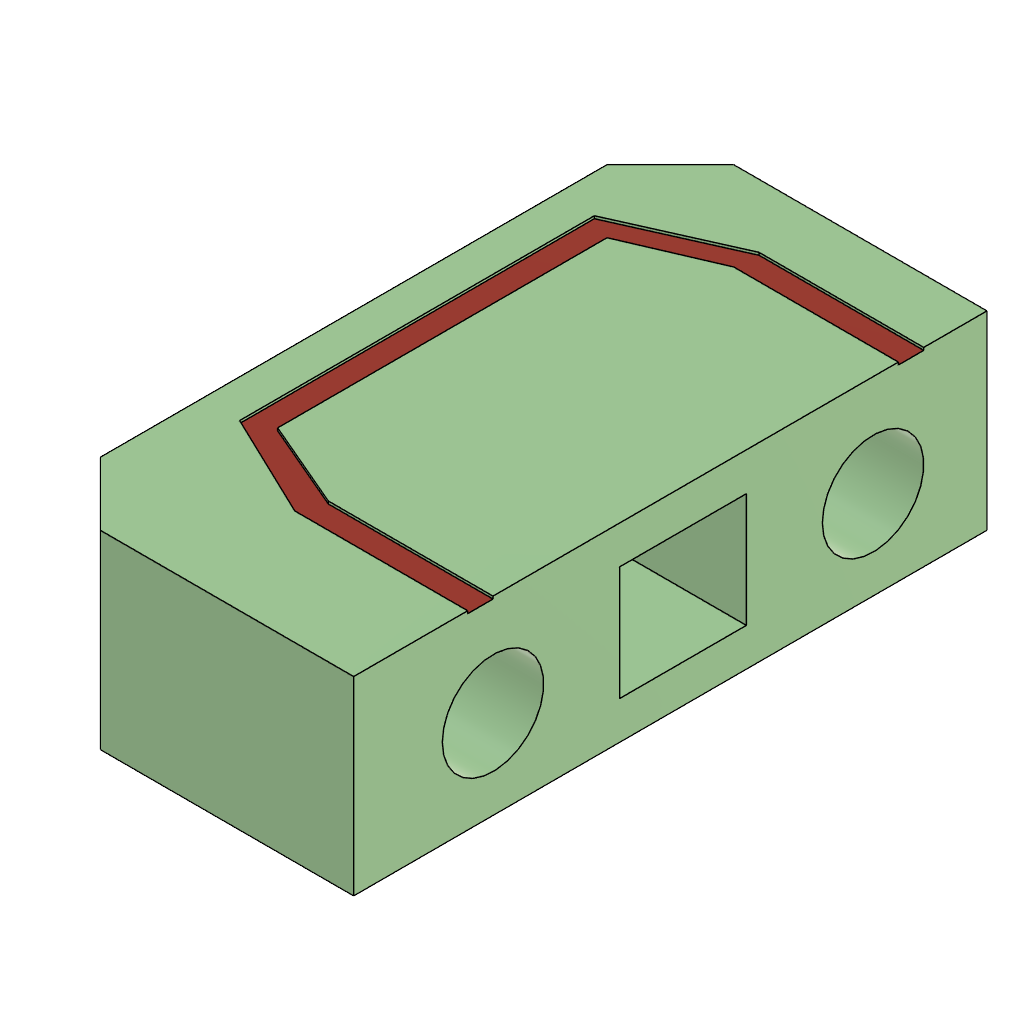
FABR (assembled) (Autodesk Fusion 360 archive; units mm, degrees)
design "Z axis end"
part number: 2026-10-14-19-35-49-229
Autodesk Fusion 360 part; units mm, degrees
note: some values were not read from the file. Set by a fixed rule: which face or edge a step refers to.
(part 1 of 2)
sketch "Sketch1" plane through (0, 0, 0) normal (0, 0, 1) x (1, 0, 0)
  line L0 (-20, 40) -> (5, 40)
  line L1 (5, 40) -> (5, -10)
  line L2 (5, -10) -> (-20, -10)
  line L3 (-20, -10) -> (-20, 40)
  dimension "d1" = 25
  dimension "d2" = 50
  constraint horizontal L0
  constraint vertical L1
  constraint horizontal L2
  constraint vertical L3
  measures "d1" distance of L0.start L0.end
  measures "d2" distance of L0.start L2.end
extrude "Extrude1" add sketch "Sketch1" along normal blind 15
sketch "Sketch2" plane through (5, 0, 0) normal (1, 0, 0) x (0, 1, 0)
  line L0 (-10, 0) -> (40, 0)
  line L1 (40, 0) -> (40, 15)
  line L2 (40, 15) -> (-10, 15)
  line L3 (-10, 15) -> (-10, 0)
  circle A0 centre (1, 7) radius 4
  circle A1 centre (31, 7) radius 4
  dimension "d5" = 8
  dimension "d6" = 8
  dimension "d7" = 30
  dimension "d8" = 8
  dimension "d9" = 8
  measures "d5" diameter of A0
  measures "d6" diameter of A1
  measures "d7" horizontal distance of A0.centre A1.centre
  measures "d8" distance of L2 A1.centre
  measures "d9" distance of L2 A0.centre
extrude "Extrude2" cut sketch "Sketch2" against normal blind 21 contours A0 | A1
sketch "Sketch3" plane through (5, 0, 0) normal (1, 0, 0) x (0, 1, 0)
  circle A0 centre (1, 7) radius 4
  circle A1 centre (31, 7) radius 4
  line L0 (-10, 0) -> (40, 0)
  line L1 (40, 0) -> (40, 15)
  line L2 (40, 15) -> (-10, 15)
  line L3 (-10, 15) -> (-10, 0)
  line L4 (11, 12) -> (21, 12)
  line L5 (21, 12) -> (21, 3)
  line L6 (21, 3) -> (11, 3)
  line L7 (11, 3) -> (11, 12)
  constraint horizontal L4
  constraint vertical L5
  constraint horizontal L6
  constraint vertical L7
extrude "Extrude3" cut sketch "Sketch3" against normal blind 18 contours L4 L5 L6 L7
sketch "Sketch4" plane through (0, 0, 3) normal (0, 0, 1) x (-1, 0, 0)
  line L0 (-5, -11) -> (-5, -21)
  line L1 (-5, -21) -> (13, -21)
  line L2 (13, -21) -> (13, -11)
  line L3 (13, -11) -> (-5, -11)
  circle A0 centre (5, -15.5) radius 2.5
  dimension "d14" = 5
  dimension "d15" = 4.5
  dimension "d16" = 10
  measures "d14" diameter of A0
  measures "d15" distance of L3 A0.centre
  measures "d16" distance of L0 A0.centre
extrude "Extrude4" add sketch "Sketch4" along normal blind 10 contours A0
extrude "Extrude5" add 1 faces at (-13, 14.3333, 9) along direction (1, 0, 0) blind 3
chamfer "Chamfer1" distance 5 angle 45 1 edges at (-20, 40, 7.5) tangent chain off
chamfer "Chamfer2" distance 5 angle 45 1 edges at (-20, -10, 7.5) tangent chain off
sketch "Sketch5" plane through (0, 0, 15) normal (0, 0, 1) x (-1, 0, 0)
  line L0 (20, 5) -> (15, 10)
  line L1 (15, 10) -> (-5, 10)
  line L2 (-5, 10) -> (-5, -40)
  line L3 (-5, -40) -> (15, -40)
  line L4 (15, -40) -> (20, -35)
  line L5 (20, -35) -> (20, 5)
  line L6 (-5, -1) -> (8, -1)
  line L7 (8, -1) -> (15, -4)
  line L8 (15, -4) -> (15, -30)
  line L9 (15, -30) -> (8, -33)
  line L10 (8, -33) -> (-5, -33)
  line L11 (-5, 1) -> (8.647, 1)
  line L12 (8.647, 1) -> (17, -3)
  line L13 (17, -3) -> (17, -31)
  line L14 (17, -31) -> (8, -35)
  line L15 (8, -35) -> (-5, -35)
  constraint coincident L2 L6.start
  constraint horizontal L6
  constraint perpendicular L6 L8
  constraint coincident L2 L10.end
  constraint perpendicular L2 L10
  constraint coincident L2 L11.start
  constraint perpendicular L2 L11
  constraint perpendicular L11 L13
  constraint coincident L2 L15.end
  constraint perpendicular L2 L15
extrude "Extrude6" cut sketch "Sketch5" against normal blind 0.2 contours L2 L6 L7 L8 L9 L10 L11 L12 L13 L14 L15
equation "d15 = 2 mm + 2.5 mm"

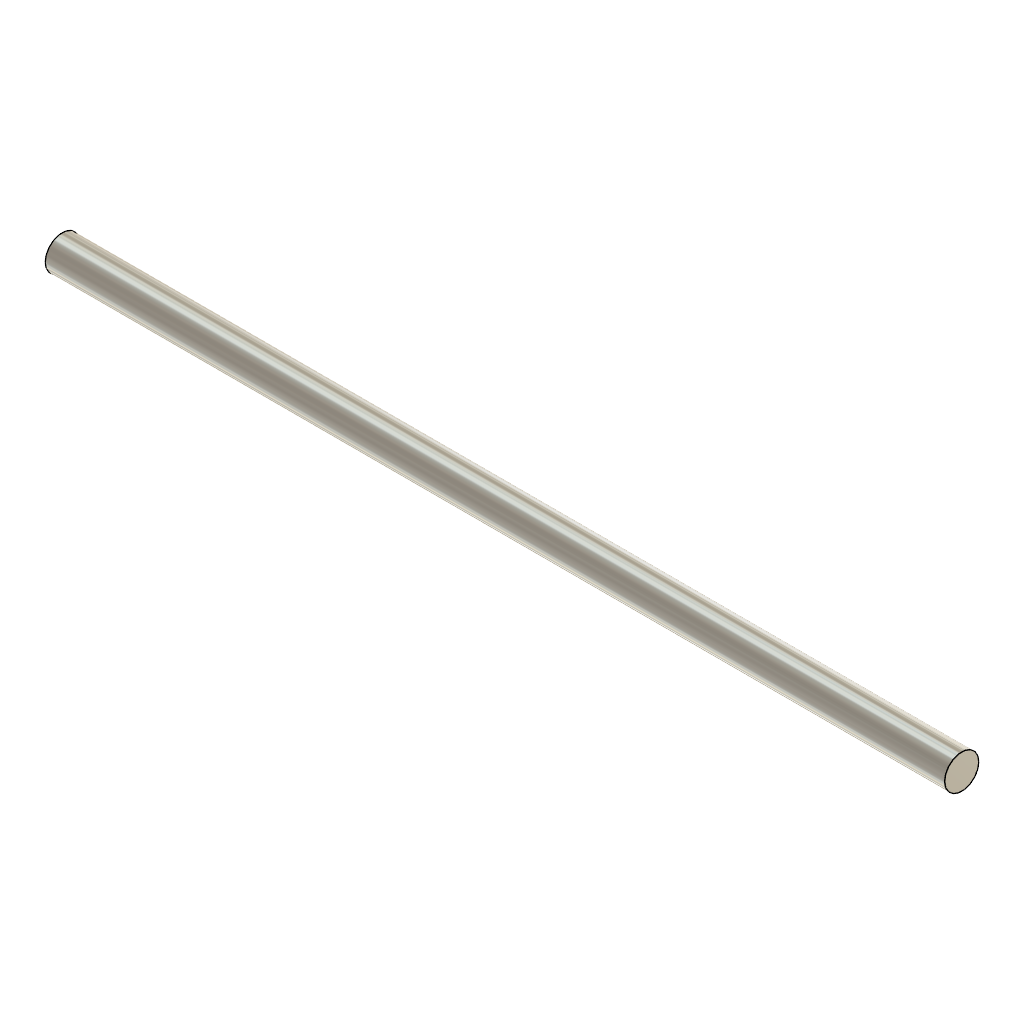
design "210mm Smooth Rod"
part number: 2026-10-15-11-29-24-474
Autodesk Fusion 360 part; units mm, degrees
sketch "Sketch1" plane through (0, 0, 0) normal (1, 0, 0) x (0, 1, 0)
  circle A0 centre (0, 0) radius 4
  dimension "d1" = 8
  constraint coincident A0.centre origin
  measures "d1" diameter of A0
extrude "Extrude1" add sketch "Sketch1" along normal blind 170
extrude "Extrude2" add 1 faces at (0, -1.2456, 0.0132) along direction (-1, 0, 0) blind 30
extrude "Extrude3" add 1 faces at (-30, -1.2456, 0.0132) along direction (-1, 0, 0) blind 10

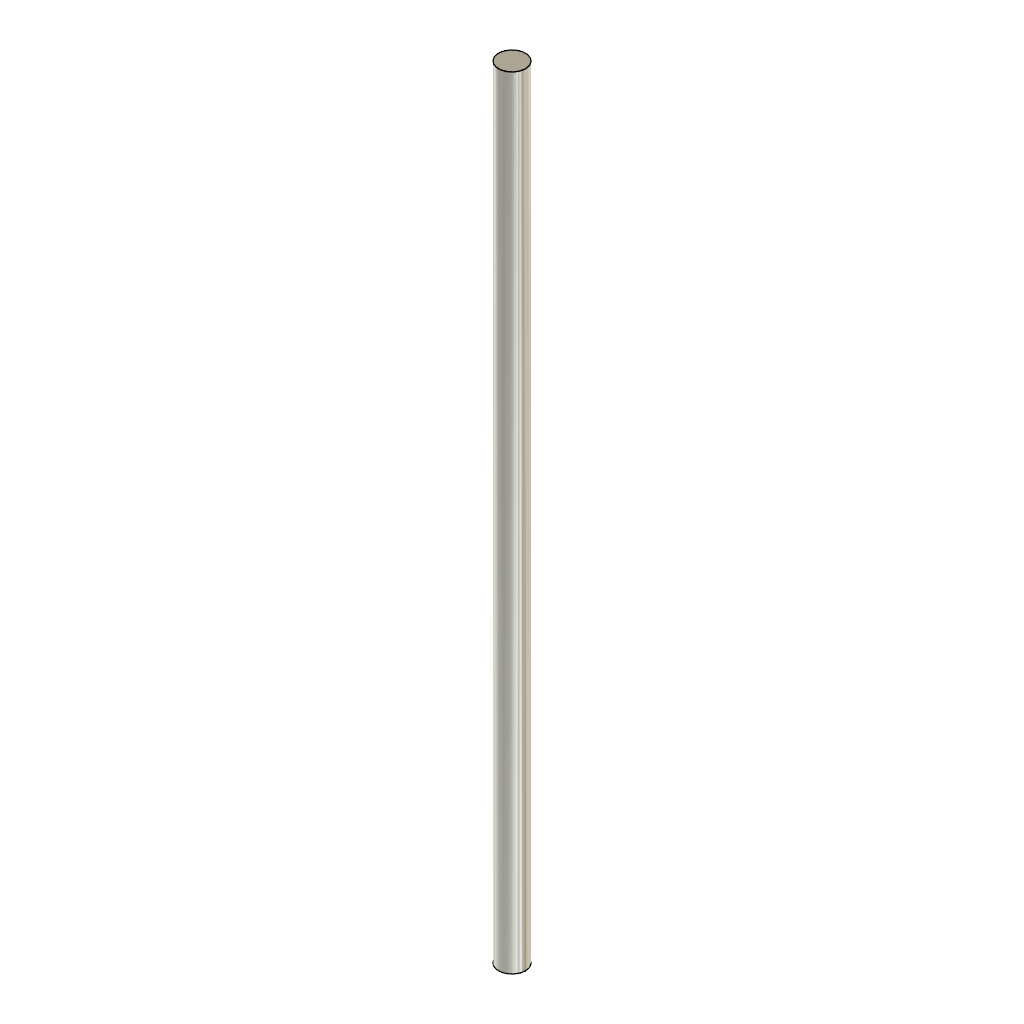
design "230mm Smooth Rod"
part number: 2026-10-14-15-24-20-619
Autodesk Fusion 360 part; units mm, degrees
sketch "Sketch1" plane through (0, 0, 0) normal (0, 0, 1) x (1, 0, 0)
  circle A0 centre (0, 0) radius 4
  dimension "d1" = 8
  constraint coincident A0.centre origin
  measures "d1" diameter of A0
extrude "Extrude1" add sketch "Sketch1" along normal blind 240
extrude "Extrude2" cut 1 faces at (-1.2456, 0.0132, 0) along direction (0, 0, 1) blind 20
extrude "Extrude3" add 1 faces at (-1.2456, 0.0132, 20) along direction (0, 0, -1) blind 10

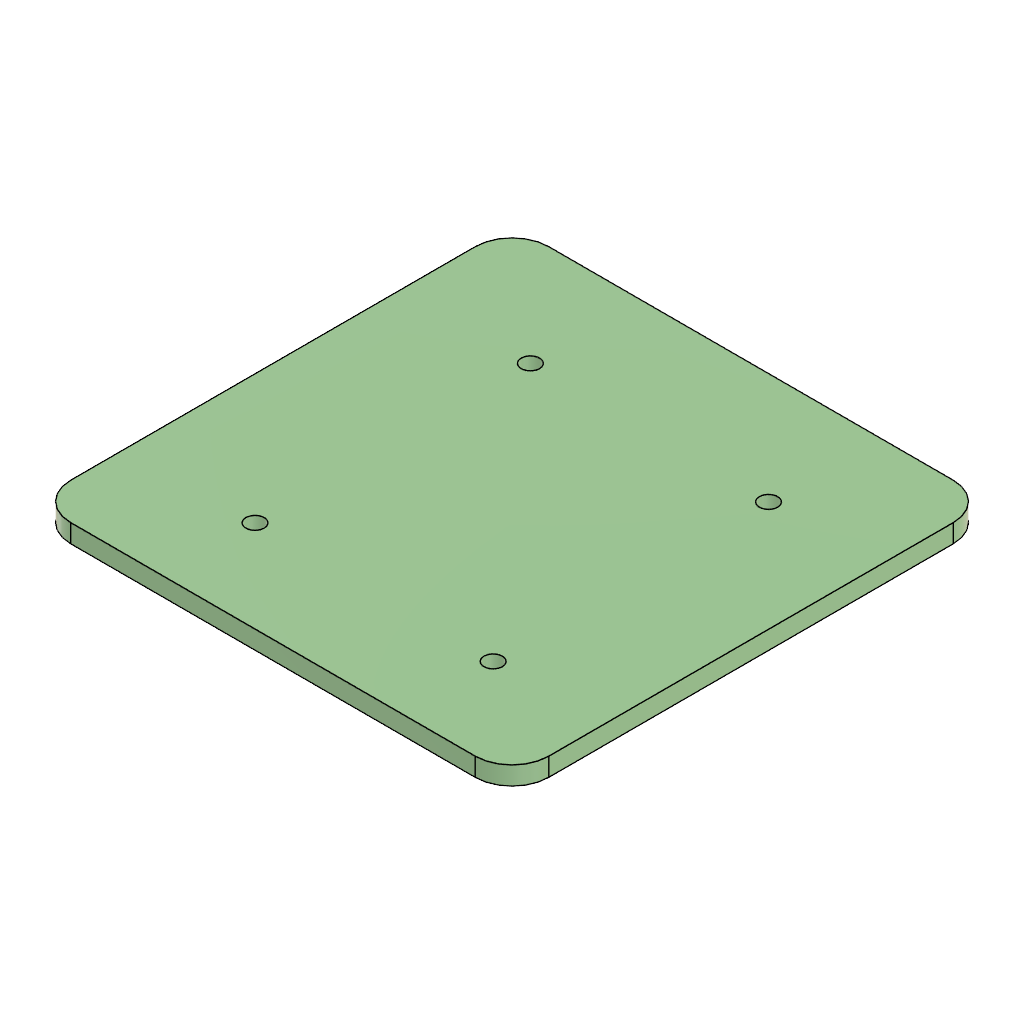
design "BED (GLASS)"
part number: 2026-10-22-09-18-17-309
Autodesk Fusion 360 part; units mm, degrees
sketch "Sketch1" plane through (0, 0, 0) normal (0, 0, 1) x (1, 0, 0)
  line L0 (-36.3354, 32.7687) -> (93.6646, 32.7687)
  line L1 (93.6646, 32.7687) -> (93.6646, -97.2313)
  line L2 (93.6646, -97.2313) -> (-36.3354, -97.2313)
  line L3 (-36.3354, -97.2313) -> (-36.3354, 32.7687)
  dimension "d1" = 130
  dimension "d2" = 130
  constraint horizontal L0
  constraint vertical L1
  constraint horizontal L2
  constraint vertical L3
  measures "d1" distance of L0.start L0.end
  measures "d2" distance of L0.start L2.end
extrude "Extrude1" add sketch "Sketch1" along normal blind 10
extrude "Extrude2" cut 1 faces at (6.998, -10.5646, 10) along direction (0, 0, -1) blind 5
sketch "Sketch2" plane through (0, 0, 5) normal (0, 0, 1) x (-1, 0, 0)
  line L0 (36.3354, 97.2313) -> (-93.6646, 97.2313)
  line L1 (-93.6646, 97.2313) -> (-93.6646, -32.7687)
  line L2 (-93.6646, -32.7687) -> (36.3354, -32.7687)
  line L3 (36.3354, -32.7687) -> (36.3354, 97.2313)
  circle A0 centre (1.3354, -2.7687) radius 2.5
  circle A1 centre (-63.6646, -2.5179) radius 2.5
  circle A2 centre (1.2136, 72.2313) radius 2.5
  circle A3 centre (-63.7864, 72.4821) radius 2.5
  dimension "d7" = 5
  dimension "d8" = 5
  dimension "d9" = 65
  dimension "d10" = 5
  dimension "d11" = 5
  dimension "d12" = 75
  dimension "d13" = 65
  dimension "d14" = 75
  dimension "d18" = 130
  dimension "d19" = 25
  measures "d7" diameter of A0
  measures "d8" diameter of A1
  measures "d9" horizontal distance of A0.centre A1.centre
  measures "d10" diameter of A2
  measures "d11" diameter of A3
  measures "d12" vertical distance of A1.centre A3.centre
  measures "d13" horizontal distance of A2.centre A3.centre
  measures "d14" vertical distance of A0.centre A2.centre
  measures "d18" distance of L0.start L0.end
  measures "d19" distance of L0 A2.centre
extrude "Extrude3" cut sketch "Sketch2" against normal blind 15 contours A0 | A1 | A2 | A3
fillet "Fillet1" radius 10 4 edges at (93.6646, -97.2313, 2.5) (-36.3354, -97.2313, 2.5) (-36.3354, 32.7687, 2.5) (93.6646, 32.7687, 2.5)
equation "a = 30 mm"

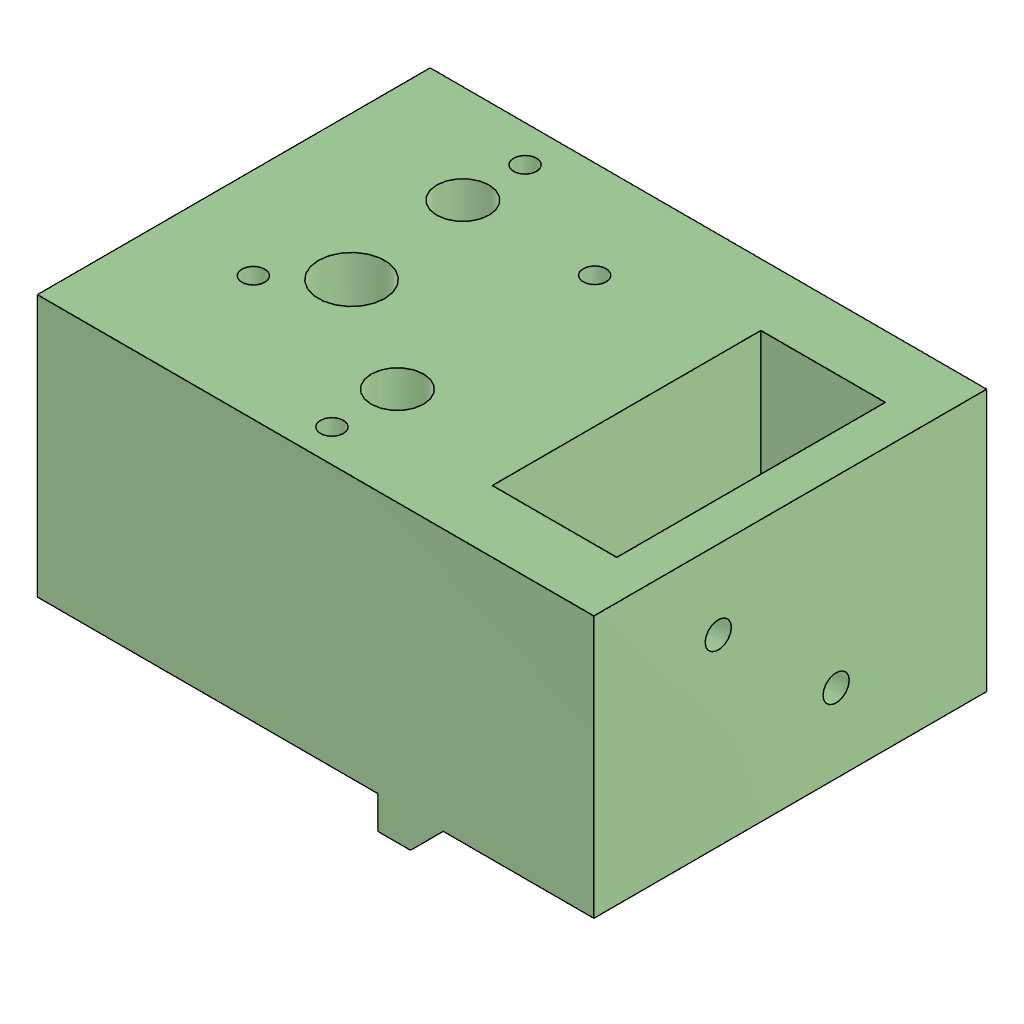
design "Y Axis Base"
part number: 2026-10-14-15-00-45-463
Autodesk Fusion 360 part; units mm, degrees
sketch "Sketch1" plane through (0, 0, 0) normal (0, 0, 1) x (1, 0, 0)
  line L0 (-30, 20) -> (30, 20)
  line L1 (30, 20) -> (30, -40)
  line L2 (30, -40) -> (-30, -40)
  line L3 (-30, -40) -> (-30, 20)
  dimension "d1" = 60
  dimension "d2" = 60
  constraint horizontal L0
  constraint vertical L1
  constraint horizontal L2
  constraint vertical L3
  measures "d1" distance of L0.start L0.end
  measures "d2" distance of L0.start L2.end
extrude "Extrude1" add sketch "Sketch1" along normal blind 40
extrude "Extrude2" add 1 faces at (30, 0, 13.3333) along direction (1, 0, 0) blind 25
sketch "Sketch2" plane through (0, 0, 40) normal (0, 0, 1) x (-1, 0, 0)
  line L0 (30, 40) -> (-55, 40)
  line L1 (-55, 40) -> (-55, -20)
  line L2 (-55, -20) -> (30, -20)
  line L3 (30, -20) -> (30, 40)
  line L4 (-30, -10.5) -> (-49, -10.5)
  line L5 (-49, -10.5) -> (-49, 30.5)
  line L6 (-49, 30.5) -> (-30, 30.5)
  line L7 (-30, 30.5) -> (-30, -10.5)
  dimension "d7" = 19
  dimension "d8" = 41
  dimension "d9" = 6
  dimension "d10" = 9.5
  dimension "d11" = 9.5
  constraint horizontal L4
  constraint vertical L5
  constraint horizontal L6
  constraint vertical L7
  measures "d7" distance of L4.start L4.end
  measures "d8" distance of L4.start L6.end
  measures "d9" distance of L1 L5
  measures "d10" distance of L2 L4
  measures "d11" distance of L0 L6
extrude "Extrude3" cut sketch "Sketch2" against normal blind 50 contours L4 L5 L6 L7
sketch "Sketch3" plane through (0, 0, 40) normal (0, 0, 1) x (-1, 0, 0)
  line L0 (-49, -10.5) -> (-49, 30.5)
  line L1 (-49, 30.5) -> (-30, 30.5)
  line L2 (-30, 30.5) -> (-30, -10.5)
  line L3 (-30, -10.5) -> (-49, -10.5)
  line L4 (30, 40) -> (-55, 40)
  line L5 (-55, 40) -> (-55, -20)
  line L6 (-55, -20) -> (30, -20)
  line L7 (30, -20) -> (30, 40)
  circle A0 centre (10, -5) radius 4
  circle A1 centre (-10, 25) radius 4
  dimension "d14" = 8
  dimension "d15" = 8
  dimension "d24" = 15
  measures "d14" diameter of A0
  measures "d15" diameter of A1
  measures "d24" distance of L4 A1.centre
extrude "Extrude4" cut sketch "Sketch3" against normal blind 20 contours A0 | A1
sketch "Sketch4" plane through (0, 0, 40) normal (0, 0, 1) x (-1, 0, 0)
  circle A0 centre (-10, 25) radius 4
  circle A1 centre (10, -5) radius 4
  line L0 (-49, -10.5) -> (-49, 30.5)
  line L1 (-49, 30.5) -> (-30, 30.5)
  line L2 (-30, 30.5) -> (-30, -10.5)
  line L3 (-30, -10.5) -> (-49, -10.5)
  line L4 (30, 40) -> (-55, 40)
  line L5 (-55, 40) -> (-55, -20)
  line L6 (-55, -20) -> (30, -20)
  line L7 (30, -20) -> (30, 40)
  circle A2 centre (16, 21) radius 1.75
  circle A3 centre (-10.0044, -5.1223) radius 1.75
  circle A4 centre (-10, 35) radius 1.75
  circle A5 centre (9.9184, -14.4189) radius 1.75
  dimension "d18" = 3.5
  dimension "d19" = 3.5
  dimension "d20" = 3.5
  dimension "d21" = 3.5
  measures "d18" diameter of A2
  measures "d19" diameter of A3
  measures "d20" diameter of A4
  measures "d21" diameter of A5
extrude "Extrude5" cut sketch "Sketch4" against normal blind 60 contours A2 | A3 | A4 | A5
sketch "Sketch5" plane through (0, 0, 40) normal (0, 0, 1) x (-1, 0, 0)
  line L0 (30, 40) -> (-55, 40)
  line L1 (-55, 40) -> (-55, -20)
  line L2 (-55, -20) -> (30, -20)
  line L3 (30, -20) -> (30, 40)
  line L4 (-49, -10.5) -> (-49, 30.5)
  line L5 (-49, 30.5) -> (-30, 30.5)
  line L6 (-30, 30.5) -> (-30, -10.5)
  line L7 (-30, -10.5) -> (-49, -10.5)
  circle A0 centre (10, -5) radius 4
  circle A1 centre (-10, 25) radius 4
  circle A2 centre (16, 21) radius 1.75
  circle A3 centre (9.9184, -14.4189) radius 1.75
  circle A4 centre (-10, 35) radius 1.75
  circle A5 centre (-10.0044, -5.1223) radius 1.75
  circle A6 centre (-1.9559, 6.9426) radius 4.75
  dimension "d25" = 9.5
  measures "d25" diameter of A6
extrude "Extrude6" cut sketch "Sketch5" against normal blind 10 contours A6
sketch "Sketch6" plane through (0, 0, 0) normal (0, 0, -1) x (1, 0, 0)
  line L0 (55, 40) -> (-30, 40)
  line L1 (-30, 40) -> (-30, -20)
  line L2 (-30, -20) -> (55, -20)
  line L3 (55, -20) -> (55, 40)
  line L4 (49, 30.5) -> (49, -10.5)
  line L5 (49, -10.5) -> (30, -10.5)
  line L6 (30, -10.5) -> (30, 30.5)
  line L7 (30, 30.5) -> (49, 30.5)
  circle A0 centre (-16, 21) radius 1.75
  circle A1 centre (-9.9184, -14.4189) radius 1.75
  circle A2 centre (10, 35) radius 1.75
  circle A3 centre (10.0044, -5.1223) radius 1.75
  line L8 (22, 40) -> (27, 40)
  line L9 (27, 40) -> (27, 32)
  line L10 (27, 32) -> (22, 32)
  line L11 (22, 32) -> (22, 40)
  line L12 (27, -20) -> (22, -20)
  line L13 (22, -20) -> (22, -12)
  line L14 (22, -12) -> (27, -12)
  line L15 (27, -12) -> (27, -20)
  dimension "d28" = 5
  dimension "d29" = 8
  dimension "d30" = 28
  dimension "d31" = 28
  dimension "d34" = 8
  constraint horizontal L8
  constraint vertical L9
  constraint horizontal L10
  constraint vertical L11
  constraint coincident L0 L8.start
  constraint horizontal L12
  constraint vertical L13
  constraint horizontal L14
  constraint vertical L15
  constraint coincident L2 L12.start
  measures "d28" distance of L12.start L12.end
  measures "d29" distance of L12.start L14.end
  measures "d30" distance of L3 L9
  measures "d31" distance of L3 L15
  measures "d34" distance of L8 L10
extrude "Extrude7" add sketch "Sketch6" along normal blind 5 contours L0 L8 L9 L10 L11 | L2 L12 L13 L14 L15
chamfer "Chamfer1" distance 5 angle 45 2 edges at (27, -36, 0) (27, 16, 0) tangent chain off
sketch "Sketch7" plane through (55, 0, 0) normal (1, 0, 0) x (0, 1, 0)
  line L0 (-40, 0) -> (20, 0)
  line L1 (20, 0) -> (20, 40)
  line L2 (20, 40) -> (-40, 40)
  line L3 (-40, 40) -> (-40, 0)
  circle A0 centre (-21, 28) radius 2
  circle A1 centre (-3, 12) radius 2
  dimension "d36" = 4
  dimension "d37" = 4
  measures "d36" diameter of A0
  measures "d37" diameter of A1
extrude "Extrude8" cut sketch "Sketch7" against normal blind 19 contours A0 | A1
extrude "Extrude9" add 1 faces at (1.7511, -5.5839, 30) along direction (0, 0, 1) blind 10
sketch "Sketch8" plane through (0, 0, 40) normal (0, 0, 1) x (-1, 0, 0)
  circle A0 centre (-10.0044, -5.1223) radius 1.75
  circle A1 centre (-10, 35) radius 1.75
  circle A2 centre (9.9184, -14.4189) radius 1.75
  circle A3 centre (16, 21) radius 1.75
  circle A4 centre (-10, 25) radius 4
  circle A5 centre (10, -5) radius 4
  line L0 (-49, -10.5) -> (-49, 30.5)
  line L1 (-49, 30.5) -> (-30, 30.5)
  line L2 (-30, 30.5) -> (-30, -10.5)
  line L3 (-30, -10.5) -> (-49, -10.5)
  line L4 (30, 40) -> (-55, 40)
  line L5 (-55, 40) -> (-55, -20)
  line L6 (-55, -20) -> (30, -20)
  line L7 (30, -20) -> (30, 40)
  circle A6 centre (8, 14) radius 5.0616
extrude "Extrude10" cut sketch "Sketch8" against normal blind 25 contours A6
equation "d24 = 20.00 mm - 5 mm"
equation "d30 = 33 mm - 5 mm"
equation "d31 = d30"

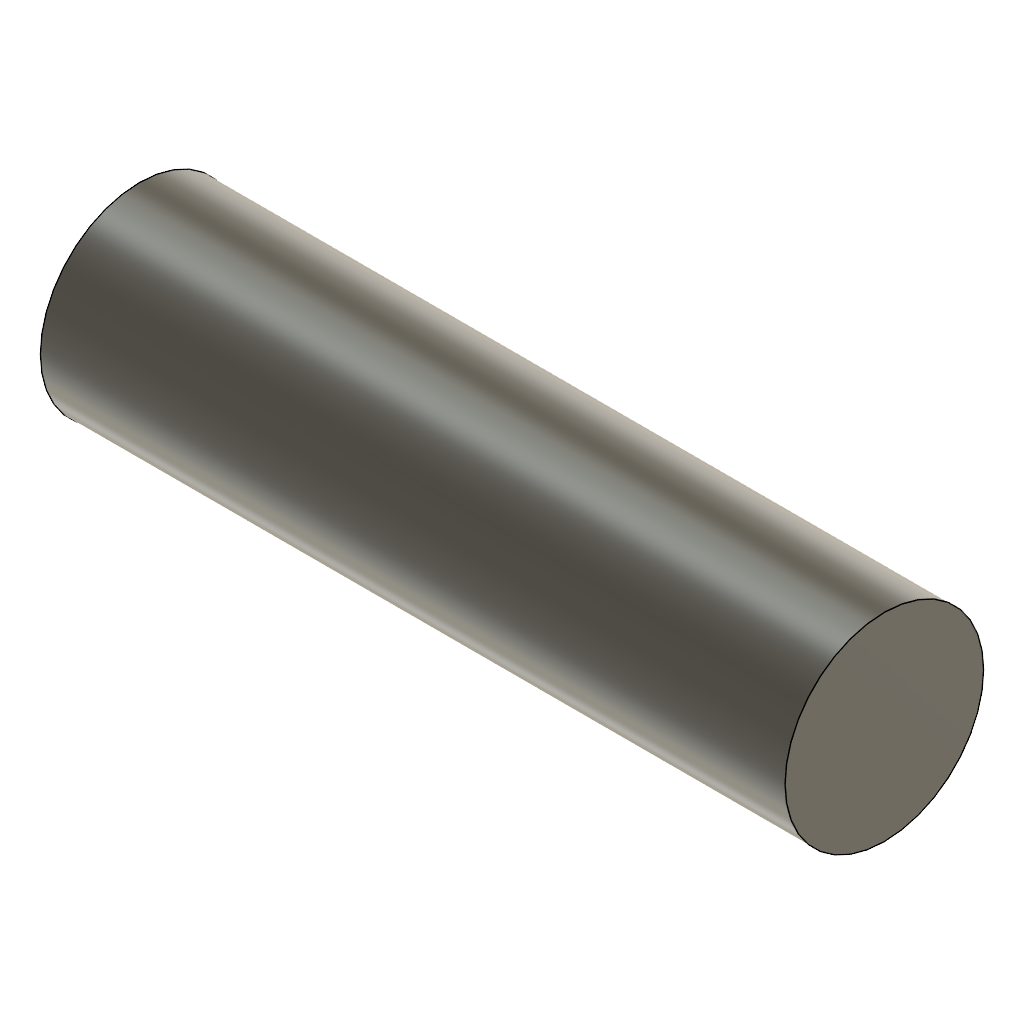
design "30mm Smooth Rod (For bearing)"
part number: 2026-10-21-11-54-07-213
Autodesk Fusion 360 part; units mm, degrees
sketch "Sketch1" plane through (0, 0, 0) normal (1, 0, 0) x (0, 1, 0)
  circle A0 centre (0, 0) radius 4
  dimension "d1" = 8
  constraint coincident A0.centre origin
  measures "d1" diameter of A0
extrude "Extrude1" add sketch "Sketch1" along normal blind 30

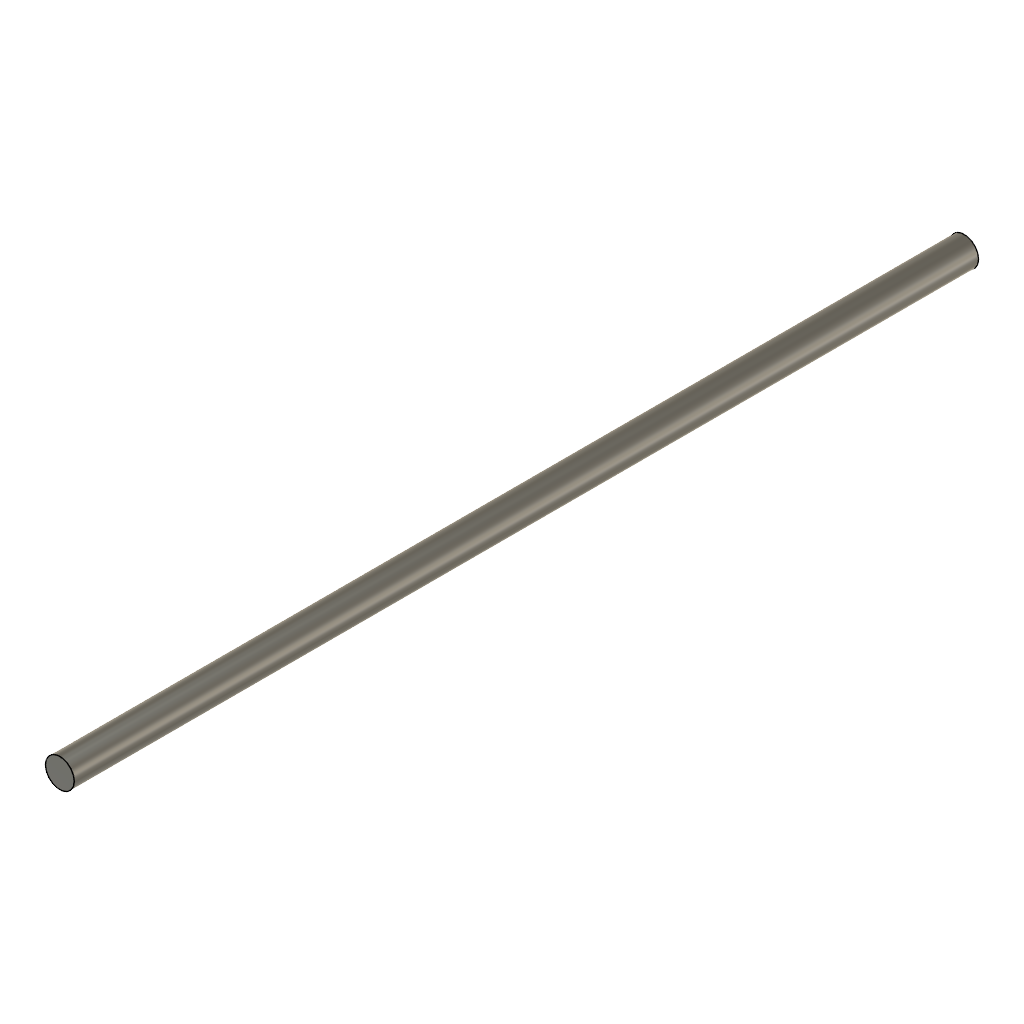
design "Smooth Rod (250mm)"
part number: 2026-10-14-14-20-23-236
Autodesk Fusion 360 part; units mm, degrees
sketch "Sketch1" plane through (0, 0, 0) normal (0, 1, 0) x (1, 0, 0)
  circle A0 centre (0, 0) radius 4
  dimension "d1" = 8
  constraint coincident A0.centre origin
  measures "d1" diameter of A0
extrude "Extrude1" add sketch "Sketch1" along normal blind 250

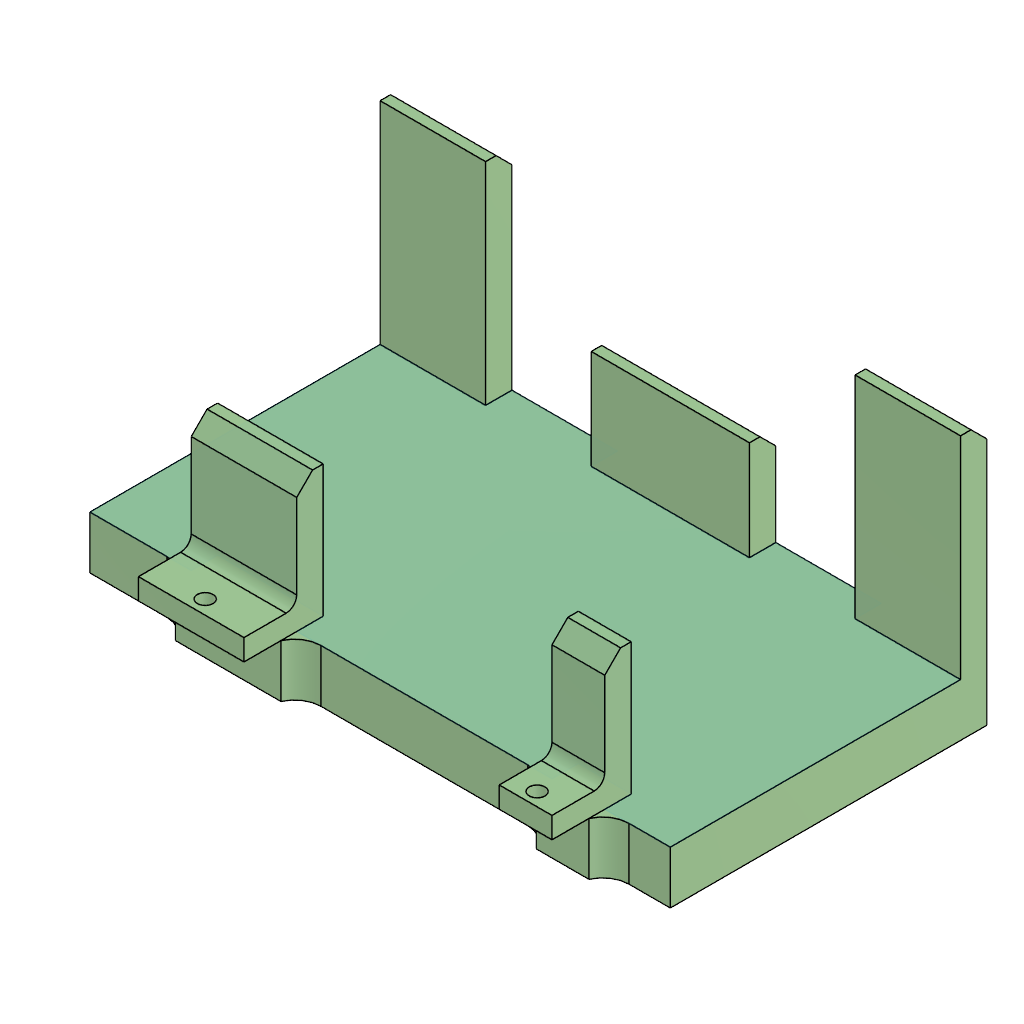
design "PSU HOLDER"
part number: 2026-10-28-12-46-23-017
Autodesk Fusion 360 part; units mm, degrees
sketch "Sketch1" plane through (0, 0, 0) normal (0, 0, 1) x (1, 0, 0)
  line L0 (-4.2354, 8.4708) -> (105.7646, 8.4708)
  line L1 (105.7646, 8.4708) -> (105.7646, -51.5292)
  line L2 (105.7646, -51.5292) -> (-4.2354, -51.5292)
  line L3 (-4.2354, -51.5292) -> (-4.2354, 8.4708)
  dimension "d1" = 110
  dimension "d2" = 60
  constraint horizontal L0
  constraint vertical L1
  constraint horizontal L2
  constraint vertical L3
  measures "d1" distance of L0.start L0.end
  measures "d2" distance of L0.start L2.end
extrude "Extrude1" add sketch "Sketch1" along normal blind 5
sketch "Sketch2" plane through (0, 0, 5) normal (0, 0, 1) x (-1, 0, 0)
  line L0 (4.2354, 51.5292) -> (-105.7646, 51.5292)
  line L1 (-105.7646, 51.5292) -> (-105.7646, -8.4708)
  line L2 (-105.7646, -8.4708) -> (4.2354, -8.4708)
  line L3 (4.2354, -8.4708) -> (4.2354, 51.5292)
  line L4 (4.2354, -8.4708) -> (-105.7646, -8.4708)
  line L5 (-105.7646, -8.4708) -> (-105.7646, -3.4708)
  line L6 (-105.7646, -3.4708) -> (4.2354, -3.4708)
  line L7 (4.2354, -3.4708) -> (4.2354, -8.4708)
  line L8 (-14.7881, 51.5292) -> (-34.7881, 51.5292)
  line L9 (-34.7881, 51.5292) -> (-34.7881, 46.5292)
  line L10 (-34.7881, 46.5292) -> (-14.7881, 46.5292)
  line L11 (-14.7881, 46.5292) -> (-14.7881, 51.5292)
  line L12 (-97.3411, 51.5292) -> (-87.3411, 51.5292)
  line L13 (-87.3411, 51.5292) -> (-87.3411, 46.5292)
  line L14 (-87.3411, 46.5292) -> (-97.3411, 46.5292)
  line L15 (-97.3411, 46.5292) -> (-97.3411, 51.5292)
  dimension "d5" = 5
  dimension "d6" = 20
  dimension "d7" = 5
  dimension "d8" = 10
  dimension "d9" = 5
  constraint horizontal L4
  constraint vertical L5
  constraint horizontal L6
  constraint vertical L7
  constraint coincident L2.end L3.start
  constraint horizontal L8
  constraint vertical L9
  constraint horizontal L10
  constraint vertical L11
  constraint coincident L0 L8.start
  constraint horizontal L12
  constraint vertical L13
  constraint horizontal L14
  constraint vertical L15
  constraint coincident L0 L12.start
  measures "d5" distance of L2.end L6.end
  measures "d6" distance of L8.start L8.end
  measures "d7" distance of L8.start L10.end
  measures "d8" distance of L12.start L12.end
  measures "d9" distance of L12.start L14.end
extrude "Extrude2" add sketch "Sketch2" along normal blind 40 contours L1 L2 L3 L4 L5 L6 L7
sketch "Sketch3" plane through (0, 0, 5) normal (0, 0, 1) x (-1, 0, 0)
  line L0 (-105.7646, -3.4708) -> (4.2354, -3.4708)
  line L1 (4.2354, -3.4708) -> (4.2354, 51.5292)
  line L2 (4.2354, 51.5292) -> (-105.7646, 51.5292)
  line L3 (-105.7646, 51.5292) -> (-105.7646, -3.4708)
  line L4 (-14.9783, 51.5292) -> (-34.9783, 51.5292)
  line L5 (-34.9783, 51.5292) -> (-34.9783, 46.5292)
  line L6 (-34.9783, 46.5292) -> (-14.9783, 46.5292)
  line L7 (-14.9783, 46.5292) -> (-14.9783, 51.5292)
  line L8 (-83.3455, 51.5292) -> (-93.3455, 51.5292)
  line L9 (-93.3455, 51.5292) -> (-93.3455, 46.5292)
  line L10 (-93.3455, 46.5292) -> (-83.3455, 46.5292)
  line L11 (-83.3455, 46.5292) -> (-83.3455, 51.5292)
  dimension "d12" = 20
  dimension "d13" = 5
  dimension "d14" = 10
  dimension "d15" = 5
  constraint horizontal L4
  constraint vertical L5
  constraint horizontal L6
  constraint vertical L7
  constraint coincident L2 L4.start
  constraint horizontal L8
  constraint vertical L9
  constraint horizontal L10
  constraint vertical L11
  constraint coincident L2 L8.start
  measures "d12" distance of L4.start L4.end
  measures "d13" distance of L4.start L6.end
  measures "d14" distance of L8.start L8.end
  measures "d15" distance of L8.start L10.end
extrude "Extrude3" add sketch "Sketch3" along normal blind 25 contours L2 L8 L9 L10 L11 | L2 L4 L5 L6 L7
sketch "Sketch4" plane through (0, -51.5292, 0) normal (0, -1, 0) x (1, 0, 0)
  line L0 (-4.2354, 0) -> (105.7646, 0)
  line L1 (105.7646, 0) -> (105.7646, 5)
  line L2 (105.7646, 5) -> (93.3455, 5)
  line L3 (93.3455, 5) -> (93.3455, 30)
  line L4 (93.3455, 30) -> (83.3455, 30)
  line L5 (83.3455, 30) -> (83.3455, 5)
  line L6 (83.3455, 5) -> (34.9783, 5)
  line L7 (34.9783, 5) -> (34.9783, 30)
  line L8 (34.9783, 30) -> (14.9783, 30)
  line L9 (14.9783, 30) -> (14.9783, 5)
  line L10 (14.9783, 5) -> (-4.2354, 5)
  line L11 (-4.2354, 5) -> (-4.2354, 0)
  line L12 (14.9783, 5) -> (34.9783, 5)
  line L13 (34.9783, 5) -> (34.9783, 9)
  line L14 (34.9783, 9) -> (14.9783, 9)
  line L15 (14.9783, 9) -> (14.9783, 5)
  line L16 (83.3455, 5) -> (93.3455, 5)
  line L17 (93.3455, 5) -> (93.3455, 9)
  line L18 (93.3455, 9) -> (83.3455, 9)
  line L19 (83.3455, 9) -> (83.3455, 5)
  dimension "d18" = 4
  dimension "d19" = 4
  constraint horizontal L12
  constraint vertical L13
  constraint horizontal L14
  constraint vertical L15
  constraint coincident L9.end L10.start
  constraint horizontal L16
  constraint vertical L17
  constraint horizontal L18
  constraint vertical L19
  constraint coincident L5.end L6.start
  measures "d18" distance of L9.end L14.end
  measures "d19" distance of L5.end L18.end
  measures "d53" diameter of L4.end
extrude "Extrude4" add sketch "Sketch4" along normal blind 7 contours L7 L9 L12 L13 L14 L15 | L3 L5 L16 L17 L18 L19
fillet "Fillet1" radius 2 2 edges at (24.9783, -51.5292, 9) (88.3455, -51.5292, 9)
chamfer "Chamfer1" distance 3 angle 45 3 edges at (24.9783, -51.5292, 30) (88.3455, -51.5292, 30) (50.7646, 8.4708, 45) tangent chain off
sketch "Sketch5" plane through (0, 8.4708, 0) normal (0, 1, 0) x (-1, 0, 0)
  line L0 (4.2354, 42) -> (-105.7646, 42)
  line L1 (-105.7646, 42) -> (-105.7646, 0)
  line L2 (-105.7646, 0) -> (4.2354, 0)
  line L3 (4.2354, 0) -> (4.2354, 42)
  line L4 (-65.7646, 0) -> (-35.7646, 0)
  line L5 (-35.7646, 0) -> (-35.7646, 47.7177)
  line L6 (-35.7646, 47.7177) -> (-65.7646, 47.7177)
  line L7 (-65.7646, 47.7177) -> (-65.7646, 0)
  line L8 (-35.7646, 0) -> (-15.7646, 0)
  line L9 (-15.7646, 0) -> (-15.7646, 47.8969)
  line L10 (-15.7646, 47.8969) -> (-35.7646, 47.8969)
  line L11 (-35.7646, 47.8969) -> (-35.7646, 0)
  line L12 (-65.7646, 0) -> (-85.7646, 0)
  line L13 (-85.7646, 0) -> (-85.7646, 48.865)
  line L14 (-85.7646, 48.865) -> (-65.7646, 48.865)
  line L15 (-65.7646, 48.865) -> (-65.7646, 0)
  line L16 (-65.7646, 0) -> (-35.7646, 0)
  line L17 (-35.7646, 0) -> (-35.7646, 23.8588)
  line L18 (-35.7646, 23.8588) -> (-65.7646, 23.8588)
  line L19 (-65.7646, 23.8588) -> (-65.7646, 0)
  dimension "d25" = 20
  dimension "d26" = 20
  dimension "d27" = 20
  dimension "d34" = 20
  dimension "d35" = 40
  constraint horizontal L4
  constraint vertical L5
  constraint horizontal L6
  constraint vertical L7
  constraint coincident L2 L4.start
  constraint horizontal L8
  constraint vertical L9
  constraint horizontal L10
  constraint vertical L11
  constraint horizontal L12
  constraint vertical L13
  constraint horizontal L14
  constraint vertical L15
  constraint horizontal L16
  constraint vertical L17
  constraint horizontal L18
  constraint vertical L19
  constraint midpoint L5 L17.end
  constraint coincident L4 L7.end
  measures "d25" distance of L3 L9
  measures "d26" distance of L1 L13
  measures "d27" distance of L5 L9
  measures "d34" distance of L7 L13
  measures "d35" distance of L1 L19
extrude "Extrude5" cut sketch "Sketch5" against normal blind 10 contours L0 L2 L5 L8 L9 L11 L17 | L0 L5 L9 L10 L11 | L0 L5 L7 L11 L15 L18 | L0 L5 L6 L7 L11 L15 | L0 L2 L7 L12 L13 L15 L19 | L0 L7 L13 L14 L15
extrude "Extrude6" add 2 faces at (79.0979, -1.5292, 3.3333) (22.4313, -1.5292, 1.6667) along direction (0, 1, 0) blind 10
chamfer "Chamfer2" distance 3 angle 45 1 edges at (50.7646, 8.4708, 23.8588) tangent chain off
sketch "Sketch6" plane through (0, 0, 0) normal (0, 0, -1) x (1, 0, 0)
  line L0 (-4.2354, -8.4708) -> (105.7646, -8.4708)
  line L1 (105.7646, -8.4708) -> (105.7646, 51.5292)
  line L2 (105.7646, 51.5292) -> (-4.2354, 51.5292)
  line L3 (-4.2354, 51.5292) -> (-4.2354, -8.4708)
sketch "Sketch7" plane through (0, 0, 5) normal (0, 0, 1) x (-1, 0, 0)
  line L0 (-65.7646, -3.4708) -> (-35.7646, -3.4708)
  line L1 (-35.7646, -3.4708) -> (-35.7646, -8.4708)
  line L2 (-35.7646, -8.4708) -> (-15.7646, -8.4708)
  line L3 (-15.7646, -8.4708) -> (-15.7646, -3.4708)
  line L4 (-15.7646, -3.4708) -> (4.2354, -3.4708)
  line L5 (4.2354, -3.4708) -> (4.2354, 51.5292)
  line L6 (4.2354, 51.5292) -> (-14.9783, 51.5292)
  line L7 (-14.9783, 51.5292) -> (-14.9783, 46.5292)
  line L8 (-14.9783, 46.5292) -> (-34.9783, 46.5292)
  line L9 (-34.9783, 46.5292) -> (-34.9783, 51.5292)
  line L10 (-34.9783, 51.5292) -> (-83.3455, 51.5292)
  line L11 (-83.3455, 51.5292) -> (-83.3455, 46.5292)
  line L12 (-83.3455, 46.5292) -> (-93.3455, 46.5292)
  line L13 (-93.3455, 46.5292) -> (-93.3455, 51.5292)
  line L14 (-93.3455, 51.5292) -> (-105.7646, 51.5292)
  line L15 (-105.7646, 51.5292) -> (-105.7646, -3.4708)
  line L16 (-105.7646, -3.4708) -> (-85.7646, -3.4708)
  line L17 (-85.7646, -3.4708) -> (-85.7646, -8.4708)
  line L18 (-85.7646, -8.4708) -> (-65.7646, -8.4708)
  line L19 (-65.7646, -8.4708) -> (-65.7646, -3.4708)
sketch "Sketch8" plane through (0, 0, 9) normal (0, 0, 1) x (-1, 0, 0)
  line L0 (-34.9783, 53.5292) -> (-14.9783, 53.5292)
  line L1 (-14.9783, 53.5292) -> (-14.9783, 58.5292)
  line L2 (-14.9783, 58.5292) -> (-34.9783, 58.5292)
  line L3 (-34.9783, 58.5292) -> (-34.9783, 53.5292)
extrude "Extrude8" add sketch "Sketch6" along normal blind 5
extrude "Extrude9" add 2 faces at (28.3117, -58.5292, 6.3333) (90.0122, -58.5292, 6.3333) along direction (0, -1, 0) blind 3
sketch "Sketch9" plane through (0, 0, 5) normal (0, 0, -1) x (1, 0, 0)
  line L0 (14.9783, 51.5292) -> (34.9783, 51.5292)
  line L1 (34.9783, 51.5292) -> (34.9783, 61.5292)
  line L2 (34.9783, 61.5292) -> (14.9783, 61.5292)
  line L3 (14.9783, 61.5292) -> (14.9783, 51.5292)
  line L4 (14.9783, 51.5292) -> (34.9783, 51.5292)
  line L5 (34.9783, 51.5292) -> (34.9783, 54.5292)
  line L6 (34.9783, 54.5292) -> (14.9783, 54.5292)
  line L7 (14.9783, 54.5292) -> (14.9783, 51.5292)
  dimension "d44" = 3
  constraint horizontal L4
  constraint vertical L5
  constraint horizontal L6
  constraint vertical L7
  constraint coincident L0.start L3.end
  measures "d44" distance of L0.start L6.end
extrude "Extrude10" add sketch "Sketch9" along normal blind 10 contours L0 L1 L3 L4 L5 L6 L7
sketch "Sketch10" plane through (0, 0, 5) normal (0, 0, -1) x (1, 0, 0)
  line L0 (83.3455, 51.5292) -> (93.3455, 51.5292)
  line L1 (93.3455, 51.5292) -> (93.3455, 61.5292)
  line L2 (93.3455, 61.5292) -> (83.3455, 61.5292)
  line L3 (83.3455, 61.5292) -> (83.3455, 51.5292)
  line L4 (83.3455, 51.5292) -> (93.3455, 51.5292)
  line L5 (93.3455, 51.5292) -> (93.3455, 54.5292)
  line L6 (93.3455, 54.5292) -> (83.3455, 54.5292)
  line L7 (83.3455, 54.5292) -> (83.3455, 51.5292)
  dimension "d47" = 3
  constraint horizontal L4
  constraint vertical L5
  constraint horizontal L6
  constraint vertical L7
  constraint coincident L0.start L3.end
  measures "d47" distance of L0.start L6.end
extrude "Extrude11" add sketch "Sketch10" along normal blind 10 contours L0 L1 L3 L4 L5 L6 L7
fillet "Fillet2" radius 5 4 edges at (14.9783, -51.5292, 0) (34.9783, -51.5292, 0) (93.3455, -51.5292, 0) (83.3455, -51.5292, 0)
sketch "Sketch11" plane through (0, 0, 9) normal (0, 0, 1) x (-1, 0, 0)
  line L0 (-34.9783, 53.5292) -> (-14.9783, 53.5292)
  line L1 (-14.9783, 53.5292) -> (-14.9783, 61.5292)
  line L2 (-14.9783, 61.5292) -> (-34.9783, 61.5292)
  line L3 (-34.9783, 61.5292) -> (-34.9783, 53.5292)
  circle A0 centre (-24.9783, 58.8702) radius 1.5
  circle A1 centre (-88, 59) radius 1.5
  dimension "d52" = 3
  dimension "d53" = 3
  measures "d52" diameter of A0
  measures "d53" diameter of A1
extrude "Extrude12" cut sketch "Sketch11" against normal blind 10 contours A0 | A1
equation "d26 = d25"

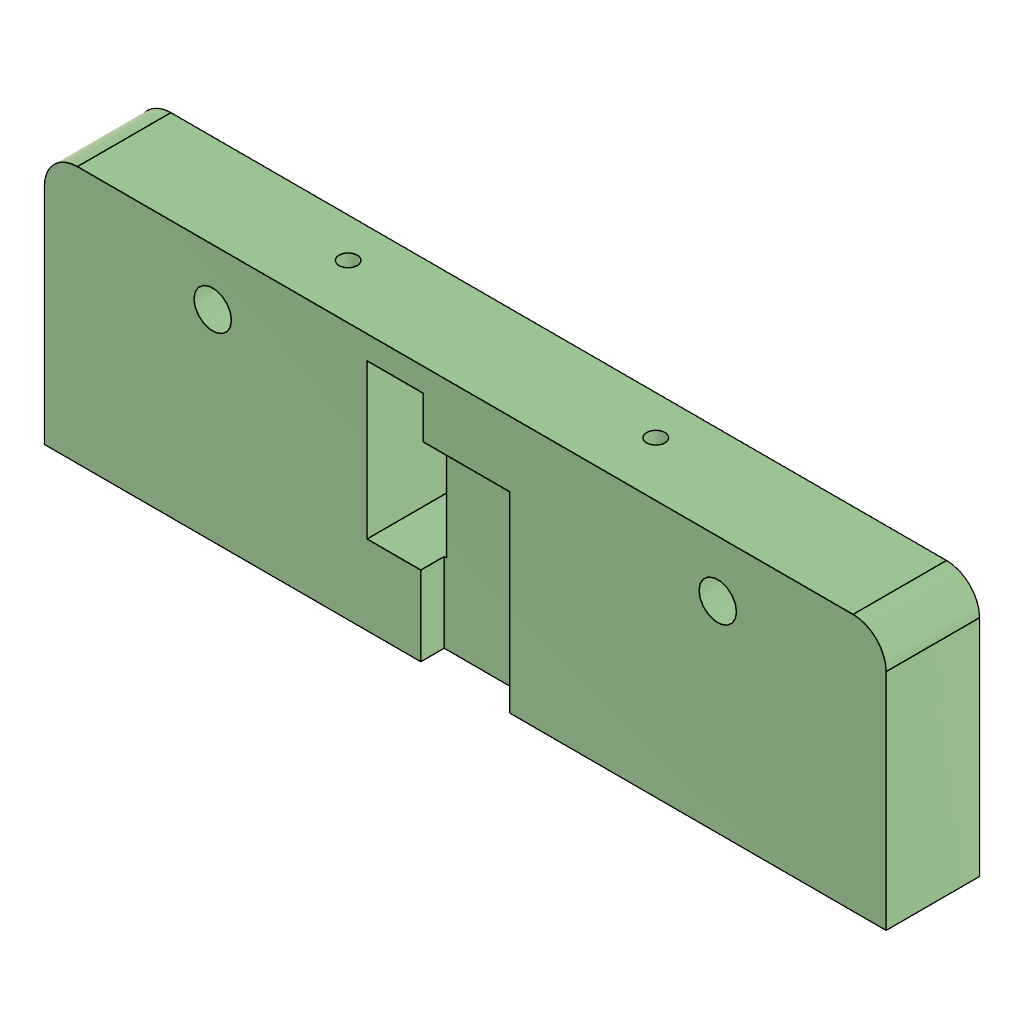
design "Rod Holder (Back Part)"
part number: 2026-10-13-20-03-55-580
Autodesk Fusion 360 part; units mm, degrees
sketch "Sketch1" plane through (0, 0, 0) normal (0, 0, 1) x (1, 0, 0)
  line L0 (-25.6354, 12.7062) -> (154.3646, 12.7062)
  line L1 (154.3646, 12.7062) -> (154.3646, -7.2938)
  line L2 (154.3646, -7.2938) -> (-25.6354, -7.2938)
  line L3 (-25.6354, -7.2938) -> (-25.6354, 12.7062)
  dimension "d1" = 180
  dimension "d2" = 20
  constraint horizontal L0
  constraint vertical L1
  constraint horizontal L2
  constraint vertical L3
  measures "d1" distance of L0.start L0.end
  measures "d2" distance of L0.start L2.end
extrude "Extrude1" add sketch "Sketch1" along normal blind 55
sketch "Sketch2" plane through (0, -7.2938, 0) normal (0, -1, 0) x (1, 0, 0)
  line L0 (-25.6354, 0) -> (154.3646, 0)
  line L1 (154.3646, 0) -> (154.3646, 55)
  line L2 (154.3646, 55) -> (-25.6354, 55)
  line L3 (-25.6354, 55) -> (-25.6354, 0)
  circle A0 centre (118.3646, 43) radius 4
  circle A1 centre (10.3646, 43) radius 4
  dimension "d5" = 8
  dimension "d6" = 8
  dimension "d7" = 12
  dimension "d8" = 36
  dimension "d9" = 12
  dimension "d10" = 36
  measures "d5" diameter of A0
  measures "d6" diameter of A1
  measures "d7" distance of L2 A0.centre
  measures "d8" distance of L1 A0.centre
  measures "d9" distance of L2 A1.centre
  measures "d10" distance of L3 A1.centre
extrude "Extrude2" cut sketch "Sketch2" against normal blind 20 contours A0 | A1
sketch "Sketch3" plane through (0, -7.2938, 0) normal (0, -1, 0) x (1, 0, 0)
  circle A0 centre (10.3646, 43) radius 4
  circle A1 centre (118.3646, 43) radius 4
  line L0 (-25.6354, 0) -> (154.3646, 0)
  line L1 (154.3646, 0) -> (154.3646, 55)
  line L2 (154.3646, 55) -> (-25.6354, 55)
  line L3 (-25.6354, 55) -> (-25.6354, 0)
  line L4 (54.8646, 41) -> (73.8646, 41)
  line L5 (73.8646, 41) -> (73.8646, 0)
  line L6 (73.8646, 0) -> (54.8646, 0)
  line L7 (54.8646, 0) -> (54.8646, 41)
  dimension "d13" = 19
  dimension "d14" = 41
  dimension "d15" = 14
  dimension "d16" = 80.5
  constraint horizontal L4
  constraint vertical L5
  constraint horizontal L6
  constraint vertical L7
  measures "d13" distance of L4.start L4.end
  measures "d14" distance of L4.start L6.end
  measures "d15" distance of L2 L4
  measures "d16" distance of L1 L5
extrude "Extrude3" cut sketch "Sketch3" against normal blind 5 contours L0 L4 L5 L6 L7
fillet "Fillet1" chord length 10 2 edges at (154.3646, 2.7062, 55) (-25.6354, 2.7062, 55)
sketch "Sketch4" plane through (0, 12.7062, 0) normal (0, 1, 0) x (-1, 0, 0)
  circle A0 centre (-10.3646, 43) radius 4
  circle A1 centre (-118.3646, 43) radius 4
  spline S0 degree 3 poles (18.5643, 55) (19.498, 55) (20.4225, 54.8151) (22.1566, 54.0924) (22.9472, 53.5577) (24.246, 52.2352) (24.7517, 51.4704) (25.4531, 49.7741) (25.6354, 48.856) (25.6354, 47.9289) knots 0 0 0 0 0.280098 0.280098 0.563604 0.563604 0.836161 0.836161 1.114279 1.114279 1.114279 1.114279
  line L0 (18.5643, 55) -> (-147.2935, 55)
  spline S1 degree 3 poles (-154.3646, 47.9289) (-154.3646, 48.8626) (-154.1797, 49.7871) (-153.457, 51.5212) (-152.9223, 52.3119) (-151.5999, 53.6106) (-150.835, 54.1163) (-149.1387, 54.8177) (-148.2206, 55) (-147.2935, 55) knots 0 0 0 0 0.280098 0.280098 0.563604 0.563604 0.836161 0.836161 1.114279 1.114279 1.114279 1.114279
  line L1 (-154.3646, 47.9289) -> (-154.3646, 0)
  line L2 (-154.3646, 0) -> (25.6354, 0)
  line L3 (25.6354, 0) -> (25.6354, 47.9289)
  circle A2 centre (-105.7846, 39.904) radius 2
  circle A3 centre (-105.7846, 9.913) radius 2
  circle A4 centre (-63.7686, 39.873) radius 2
  circle A5 centre (-63.7696, 9.897) radius 2
  dimension "d21" = 4
  dimension "d22" = 15.096
  dimension "d23" = 48.58
  dimension "d24" = 4
  dimension "d25" = 9.913
  dimension "d26" = 48.58
  dimension "d27" = 4
  dimension "d28" = 15.127
  dimension "d29" = 4
  dimension "d30" = 45.103
  dimension "d31" = 90.596
  dimension "d32" = 90.595
  measures "d21" diameter of A2
  measures "d22" distance of L0 A2.centre
  measures "d23" distance of L1 A2.centre
  measures "d24" diameter of A3
  measures "d25" distance of L2 A3.centre
  measures "d26" distance of L1 A3.centre
  measures "d27" diameter of A4
  measures "d28" distance of L0 A4.centre
  measures "d29" diameter of A5
  measures "d30" distance of L0 A5.centre
  measures "d31" distance of L1 A4.centre
  measures "d32" distance of L1 A5.centre
extrude "Extrude4" cut sketch "Sketch4" against normal blind 1 contours A2 | A3 | A4 | A5
sketch "Sketch5" plane through (0, 12.7062, 0) normal (0, 1, 0) x (-1, 0, 0)
  spline S0 degree 3 poles (18.5643, 55) (19.498, 55) (20.4225, 54.8151) (22.1566, 54.0924) (22.9472, 53.5577) (24.246, 52.2352) (24.7517, 51.4704) (25.4531, 49.7741) (25.6354, 48.856) (25.6354, 47.9289) knots 0 0 0 0 0.280098 0.280098 0.563604 0.563604 0.836161 0.836161 1.114279 1.114279 1.114279 1.114279
  line L0 (18.5643, 55) -> (-147.2935, 55)
  spline S1 degree 3 poles (-154.3646, 47.9289) (-154.3646, 48.8626) (-154.1797, 49.7871) (-153.457, 51.5212) (-152.9223, 52.3119) (-151.5999, 53.6106) (-150.835, 54.1163) (-149.1387, 54.8177) (-148.2206, 55) (-147.2935, 55) knots 0 0 0 0 0.280098 0.280098 0.563604 0.563604 0.836161 0.836161 1.114279 1.114279 1.114279 1.114279
  line L1 (-154.3646, 47.9289) -> (-154.3646, 0)
  line L2 (-154.3646, 0) -> (25.6354, 0)
  line L3 (25.6354, 0) -> (25.6354, 47.9289)
  circle A0 centre (-118.3646, 43) radius 4
  circle A1 centre (-10.3646, 43) radius 4
  circle A2 centre (-105.7846, 9.913) radius 2
  circle A3 centre (-105.7846, 39.904) radius 2
  circle A4 centre (-63.7696, 9.897) radius 2
  circle A5 centre (-63.7686, 39.873) radius 2
  line L4 (-55.3646, 50) -> (-43.3646, 50)
  line L5 (-43.3646, 50) -> (-43.3646, 21)
  line L6 (-43.3646, 21) -> (-55.3646, 21)
  line L7 (-55.3646, 21) -> (-55.3646, 50)
  dimension "d35" = 12
  dimension "d36" = 29
  dimension "d37" = 69
  dimension "d38" = 5
  constraint horizontal L4
  constraint vertical L5
  constraint horizontal L6
  constraint vertical L7
  measures "d35" distance of L4.start L4.end
  measures "d36" distance of L4.start L6.end
  measures "d37" distance of L3 L5
  measures "d38" distance of L0 L4
extrude "Extrude5" cut sketch "Sketch5" against normal blind 40 contours L4 L5 L6 L7
sketch "Sketch6" plane through (0, 12.7062, 0) normal (0, 1, 0) x (-1, 0, 0)
  line L0 (-43.3646, 50) -> (-43.3646, 21)
  line L1 (-43.3646, 21) -> (-55.3646, 21)
  line L2 (-55.3646, 21) -> (-55.3646, 50)
  line L3 (-55.3646, 50) -> (-43.3646, 50)
  spline S0 degree 3 poles (18.5643, 55) (19.498, 55) (20.4225, 54.8151) (22.1566, 54.0924) (22.9472, 53.5577) (24.246, 52.2352) (24.7517, 51.4704) (25.4531, 49.7741) (25.6354, 48.856) (25.6354, 47.9289) knots 0 0 0 0 0.280098 0.280098 0.563604 0.563604 0.836161 0.836161 1.114279 1.114279 1.114279 1.114279
  line L4 (18.5643, 55) -> (-147.2935, 55)
  spline S1 degree 3 poles (-154.3646, 47.9289) (-154.3646, 48.8626) (-154.1797, 49.7871) (-153.457, 51.5212) (-152.9223, 52.3119) (-151.5999, 53.6106) (-150.835, 54.1163) (-149.1387, 54.8177) (-148.2206, 55) (-147.2935, 55) knots 0 0 0 0 0.280098 0.280098 0.563604 0.563604 0.836161 0.836161 1.114279 1.114279 1.114279 1.114279
  line L5 (-154.3646, 47.9289) -> (-154.3646, 0)
  line L6 (-154.3646, 0) -> (25.6354, 0)
  line L7 (25.6354, 0) -> (25.6354, 47.9289)
  circle A0 centre (-118.3646, 43) radius 4
  circle A1 centre (-10.3646, 43) radius 4
  circle A2 centre (-105.7846, 9.913) radius 2
  circle A3 centre (-105.7846, 39.904) radius 2
  circle A4 centre (-63.7696, 9.897) radius 2
  circle A5 centre (-63.7686, 39.873) radius 2
  line L8 (-55.3646, 21) -> (-43.3646, 21)
  line L9 (-43.3646, 21) -> (-43.3646, 17)
  line L10 (-43.3646, 17) -> (-55.3646, 17)
  line L11 (-55.3646, 17) -> (-55.3646, 21)
  dimension "d41" = 4
  constraint horizontal L8
  constraint vertical L9
  constraint horizontal L10
  constraint vertical L11
  constraint coincident L1.end L2.start
  measures "d41" distance of L1.end L10.end
extrude "Extrude6" cut sketch "Sketch6" against normal blind 29 contours L1 L8 L9 L10 L11
sketch "Sketch7" plane through (0, 0, 55) normal (0, 0, 1) x (-1, 0, 0)
  line L0 (18.5643, 7.2938) -> (18.5643, -12.7062)
  line L1 (18.5643, 7.2938) -> (-147.2935, 7.2938)
  line L2 (-147.2935, -12.7062) -> (-147.2935, 7.2938)
  line L3 (-147.2935, -12.7062) -> (18.5643, -12.7062)
  circle A0 centre (-27.7445, -4.289) radius 1.95
  circle A1 centre (-93.4776, -4.3449) radius 1.95
  dimension "d44" = 3.9
  dimension "d45" = 3.9
  measures "d44" diameter of A0
  measures "d45" diameter of A1
extrude "Extrude7" cut sketch "Sketch7" against normal blind 70 contours A0 | A1
equation "d22 = 13.096 mm + 2 mm"
equation "d23 = 46.58 mm + 2 mm"
equation "d25 = 7.913 mm + 2 mm"
equation "d26 = 46.58 mm + 2 mm"
equation "d28 = 13.127 mm + 2 mm"
equation "d30 = 43.103 mm + 2 mm"
equation "d31 = 88.596 mm + 2 mm"
equation "d32 = 88.595 mm + 2 mm"

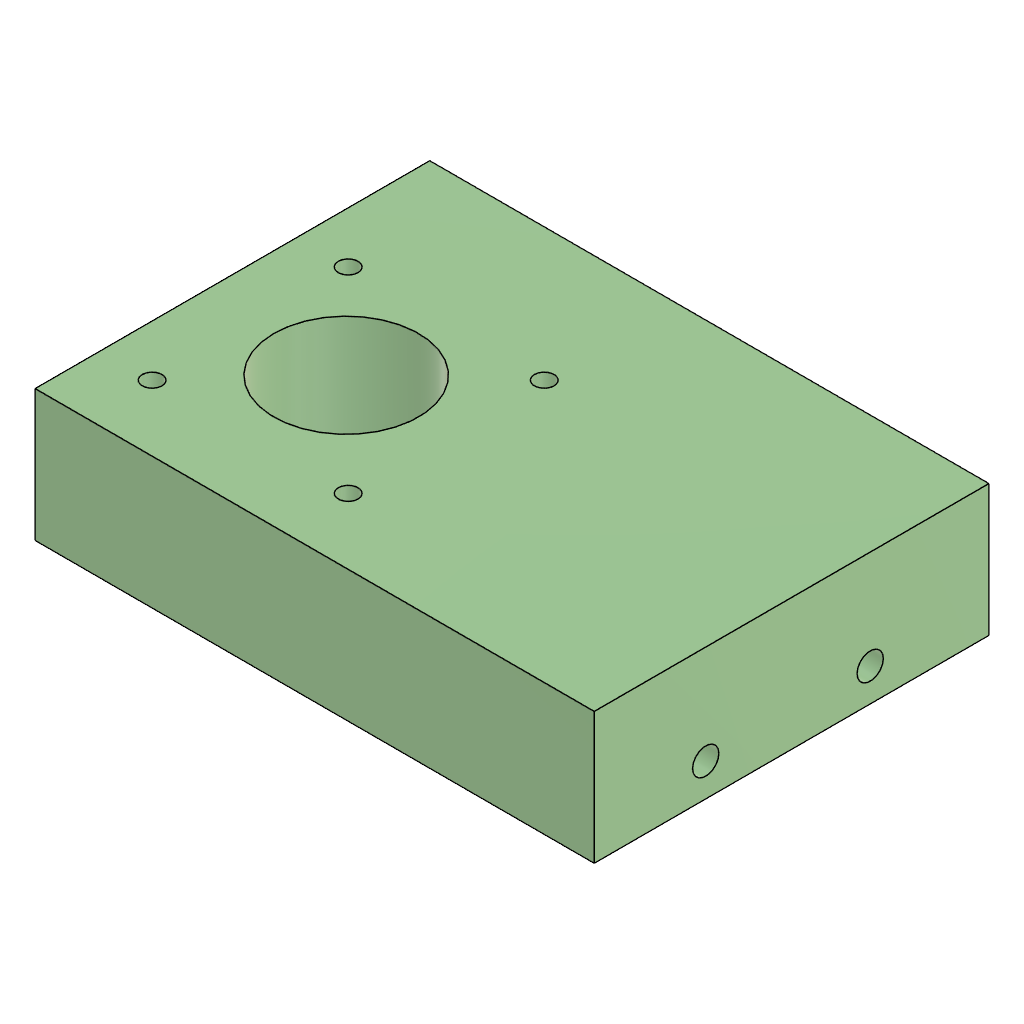
design "Y Axis Top"
part number: 2026-10-14-15-29-44-406
Autodesk Fusion 360 part; units mm, degrees
sketch "Sketch1" plane through (0, 0, 0) normal (0, 0, 1) x (1, 0, 0)
  line L0 (-14.4896, 18.0562) -> (70.5104, 18.0562)
  line L1 (70.5104, 18.0562) -> (70.5104, -41.9438)
  line L2 (70.5104, -41.9438) -> (-14.4896, -41.9438)
  line L3 (-14.4896, -41.9438) -> (-14.4896, 18.0562)
  line L4 (45.5104, 8.5562) -> (64.5104, 8.5562)
  line L5 (64.5104, 8.5562) -> (64.5104, -32.4438)
  line L6 (64.5104, -32.4438) -> (45.5104, -32.4438)
  line L7 (45.5104, -32.4438) -> (45.5104, 8.5562)
  circle A0 centre (5.5104, 3.0562) radius 4
  circle A1 centre (25.5104, -26.9438) radius 4
  dimension "d1" = 85
  dimension "d2" = 60
  dimension "d3" = 19
  dimension "d4" = 41
  dimension "d5" = 6
  dimension "d6" = 9.5
  dimension "d7" = 9.5
  dimension "d8" = 8
  dimension "d9" = 8
  dimension "d10" = 15
  dimension "d11" = 40
  dimension "d12" = 15
  dimension "d13" = 20
  constraint horizontal L0
  constraint vertical L1
  constraint horizontal L2
  constraint vertical L3
  constraint horizontal L4
  constraint vertical L5
  constraint horizontal L6
  constraint vertical L7
  measures "d1" distance of L0.start L0.end
  measures "d2" distance of L0.start L2.end
  measures "d3" distance of L4.start L4.end
  measures "d4" distance of L4.start L6.end
  measures "d5" distance of L1 L5
  measures "d6" distance of L0 L4
  measures "d7" distance of L2 L6
  measures "d8" diameter of A0
  measures "d9" diameter of A1
  measures "d10" distance of L2 A1.centre
  measures "d11" distance of L3 A1.centre
  measures "d12" distance of L0 A0.centre
  measures "d13" distance of L3 A0.centre
extrude "Extrude1" add sketch "Sketch1" along normal blind 20
sketch "Sketch2" plane through (0, 0, 0) normal (0, 0, 1) x (1, 0, 0)
sketch "Sketch4" plane through (0, 8.5562, 0) normal (0, -1, 0) x (1, 0, 0)
  line L0 (45.5104, 0) -> (64.5104, 0)
  line L1 (64.5104, 0) -> (64.5104, 20)
  line L2 (64.5104, 20) -> (45.5104, 20)
  line L3 (45.5104, 20) -> (45.5104, 0)
  line L4 (45.5104, 20) -> (64.5104, 20)
  line L5 (64.5104, 20) -> (64.5104, 8)
  line L6 (64.5104, 8) -> (45.5104, 8)
  line L7 (45.5104, 8) -> (45.5104, 20)
  dimension "d23" = 12
  constraint horizontal L4
  constraint vertical L5
  constraint horizontal L6
  constraint vertical L7
  constraint coincident L2.end L3.start
  measures "d23" distance of L2.end L6.end
extrude "Extrude4" add sketch "Sketch4" along normal blind 50 contours L1 L2 L3 L4 L5 L6 L7
sketch "Sketch5" plane through (0, 0, 0) normal (0, 0, -1) x (1, 0, 0)
  circle A0 centre (25.5104, 26.9438) radius 4
  circle A1 centre (5.5104, -3.0562) radius 4
  line L0 (45.5104, 32.4438) -> (64.5104, 32.4438)
  line L1 (64.5104, 32.4438) -> (64.5104, -8.5562)
  line L2 (64.5104, -8.5562) -> (45.5104, -8.5562)
  line L3 (45.5104, -8.5562) -> (45.5104, 32.4438)
  line L4 (70.5104, 41.9438) -> (-14.4896, 41.9438)
  line L5 (-14.4896, 41.9438) -> (-14.4896, -18.0562)
  line L6 (-14.4896, -18.0562) -> (70.5104, -18.0562)
  line L7 (70.5104, -18.0562) -> (70.5104, 41.9438)
  circle A2 centre (17.4104, 9.9438) radius 11
  dimension "d26" = 22
  dimension "d27" = 31.9
  dimension "d28" = 28
  measures "d26" diameter of A2
  measures "d27" distance of L5 A2.centre
  measures "d28" distance of L6 A2.centre
extrude "Extrude5" cut sketch "Sketch5" against normal blind 20 contours A2
sketch "Sketch6" plane through (0, 0, 0) normal (0, 0, -1) x (1, 0, 0)
  circle A0 centre (17.4104, 9.9438) radius 11
  circle A1 centre (25.5104, 26.9438) radius 4
  circle A2 centre (5.5104, -3.0562) radius 4
  line L0 (45.5104, 32.4438) -> (64.5104, 32.4438)
  line L1 (64.5104, 32.4438) -> (64.5104, -8.5562)
  line L2 (64.5104, -8.5562) -> (45.5104, -8.5562)
  line L3 (45.5104, -8.5562) -> (45.5104, 32.4438)
  line L4 (70.5104, 41.9438) -> (-14.4896, 41.9438)
  line L5 (-14.4896, 41.9438) -> (-14.4896, -18.0562)
  line L6 (-14.4896, -18.0562) -> (70.5104, -18.0562)
  line L7 (70.5104, -18.0562) -> (70.5104, 41.9438)
  circle A3 centre (17.4104, 9.9438) radius 11
  constraint concentric A0 A3
extrude "Extrude6" add sketch "Sketch6" against normal blind 20 contours A0 A3
sketch "Sketch7" plane through (0, 0, 0) normal (0, 0, -1) x (1, 0, 0)
  circle A0 centre (25.5104, 26.9438) radius 4
  circle A1 centre (5.5104, -3.0562) radius 4
  line L0 (45.5104, 32.4438) -> (64.5104, 32.4438)
  line L1 (64.5104, 32.4438) -> (64.5104, -8.5562)
  line L2 (64.5104, -8.5562) -> (45.5104, -8.5562)
  line L3 (45.5104, -8.5562) -> (45.5104, 32.4438)
  line L4 (70.5104, 41.9438) -> (-14.4896, 41.9438)
  line L5 (-14.4896, 41.9438) -> (-14.4896, -18.0562)
  line L6 (-14.4896, -18.0562) -> (70.5104, -18.0562)
  line L7 (70.5104, -18.0562) -> (70.5104, 41.9438)
  circle A2 centre (7.4104, 16.5438) radius 11
  dimension "d33" = 22
  dimension "d34" = 21.9
  dimension "d35" = 34.6
  measures "d33" diameter of A2
  measures "d34" distance of L5 A2.centre
  measures "d35" distance of L6 A2.centre
extrude "Extrude7" cut sketch "Sketch7" against normal blind 35 contours A2
sketch "Sketch8" plane through (0, 0, 20) normal (0, 0, 1) x (-1, 0, 0)
  circle A0 centre (-7.4104, 16.5438) radius 11
  circle A1 centre (-25.5104, 26.9438) radius 4
  circle A2 centre (-5.5104, -3.0562) radius 4
  line L0 (14.4896, 41.9438) -> (-70.5104, 41.9438)
  line L1 (-70.5104, 41.9438) -> (-70.5104, -18.0562)
  line L2 (-70.5104, -18.0562) -> (14.4896, -18.0562)
  line L3 (14.4896, -18.0562) -> (14.4896, 41.9438)
  circle A3 centre (-23.1104, 31.9438) radius 1.5
  circle A4 centre (6.6896, 31.9438) radius 1.5
  circle A5 centre (-25.5104, 26.9438) radius 4
  circle A6 centre (-23.1104, 2.1438) radius 1.5
  circle A7 centre (6.6896, 2.1438) radius 1.5
  dimension "d38" = 3
  dimension "d39" = 47.4
  dimension "d40" = 10
  dimension "d41" = 3
  dimension "d42" = 29.8
  dimension "d43" = 10
  dimension "d44" = 3
  dimension "d45" = 29.8
  dimension "d46" = 3
  dimension "d47" = 29.8
  dimension "d48" = 47.4
  dimension "d49" = 29.8
  constraint concentric A1 A5
  measures "d38" diameter of A3
  measures "d39" distance of L1 A3.centre
  measures "d40" distance of L0 A3.centre
  measures "d41" diameter of A4
  measures "d42" horizontal distance of A3.centre A4.centre
  measures "d43" distance of L0 A4.centre
  measures "d44" diameter of A6
  measures "d45" vertical distance of A3.centre A6.centre
  measures "d46" diameter of A7
  measures "d47" vertical distance of A4.centre A7.centre
  measures "d48" distance of L1 A6.centre
  measures "d49" distance of A6.centre A7.centre
extrude "Extrude8" cut sketch "Sketch8" against normal blind 24 contours A1 A5 | A3 | A4 | A6 | A7
sketch "Sketch9" plane through (0, 0, 20) normal (0, 0, 1) x (-1, 0, 0)
  line L0 (14.4896, 41.9438) -> (-70.5104, 41.9438)
  line L1 (-70.5104, 41.9438) -> (-70.5104, -18.0562)
  line L2 (-70.5104, -18.0562) -> (14.4896, -18.0562)
  line L3 (14.4896, -18.0562) -> (14.4896, 41.9438)
  circle A0 centre (-5.5104, -3.0562) radius 4
  circle A1 centre (-25.5104, 26.9438) radius 4
  circle A2 centre (-7.4104, 16.5438) radius 11
  circle A3 centre (6.6896, 2.1438) radius 1.5
  circle A4 centre (-23.1104, 31.9438) radius 1.5
  circle A5 centre (6.6896, 31.9438) radius 1.5
  circle A6 centre (-23.1104, 2.1438) radius 1.5
  circle A7 centre (-25.5104, 26.9438) radius 4
  constraint concentric A1 A7
extrude "Extrude9" add sketch "Sketch9" against normal blind 5 contours A1 A7
sketch "Sketch10" plane through (0, 0, 0) normal (1, 0, 0) x (0, 1, 0)
sketch "Sketch11" plane through (0, 0, 20) normal (0, 0, 1) x (-1, 0, 0)
  line L0 (14.4896, 41.9438) -> (-70.5104, 41.9438)
  line L1 (-70.5104, 41.9438) -> (-70.5104, -18.0562)
  line L2 (-70.5104, -18.0562) -> (14.4896, -18.0562)
  line L3 (14.4896, -18.0562) -> (14.4896, 41.9438)
  circle A0 centre (-5.5104, -3.0562) radius 4
  circle A1 centre (-7.4104, 16.5438) radius 11
  circle A2 centre (6.6896, 2.1438) radius 1.5
  circle A3 centre (-23.1104, 31.9438) radius 1.5
  circle A4 centre (6.6896, 31.9438) radius 1.5
  circle A5 centre (-23.1104, 2.1438) radius 1.5
  circle A6 centre (-5.5104, -3.0562) radius 4
  constraint concentric A0 A6
extrude "Extrude10" add sketch "Sketch11" against normal blind 5 contours A0 A6
sketch "Sketch12" plane through (70.5104, 0, 0) normal (1, 0, 0) x (0, 1, 0)
  line L0 (-41.9438, 0) -> (18.0562, 0)
  line L1 (18.0562, 0) -> (18.0562, 20)
  line L2 (18.0562, 20) -> (-41.9438, 20)
  line L3 (-41.9438, 20) -> (-41.9438, 0)
  circle A0 centre (-25, 5) radius 2
  circle A1 centre (0, 5) radius 2
  dimension "d56" = 4
  dimension "d57" = 4
  dimension "d58" = 5
  dimension "d59" = 5
  measures "d56" diameter of A0
  measures "d57" diameter of A1
  measures "d58" distance of L0 A0.centre
  measures "d59" distance of L0 A1.centre
extrude "Extrude11" cut sketch "Sketch12" against normal blind 29 contours A0 | A1
equation "d10 = 16 mm + 4 mm - 5 mm"
equation "d11 = 36 mm + 4 mm"
equation "d12 = 11 mm + 4 mm"
equation "d13 = 16 mm + 4 mm"
equation "d27 = 21.9 mm + 10 mm"
equation "d39 = 41.9 mm + 5.5 mm"

design "Base 330x230 Wood"
part number: 2026-10-14-14-57-42-910
Autodesk Fusion 360 part; units mm, degrees
sketch "Sketch1" plane through (0, 0, 0) normal (0, 0, 1) x (1, 0, 0)
  line L0 (-117.9228, 62.1937) -> (112.0772, 62.1937)
  line L1 (112.0772, 62.1937) -> (112.0772, -267.8063)
  line L2 (112.0772, -267.8063) -> (-117.9228, -267.8063)
  line L3 (-117.9228, -267.8063) -> (-117.9228, 62.1937)
  dimension "d1" = 230
  dimension "d2" = 330
  constraint horizontal L0
  constraint vertical L1
  constraint horizontal L2
  constraint vertical L3
  measures "d1" distance of L0.start L0.end
  measures "d2" distance of L0.start L2.end
extrude "Extrude1" add sketch "Sketch1" along normal blind 10

design "Custom Stepper Mount"
part number: 2026-10-26-23-26-53-679
Autodesk Fusion 360 part; units mm, degrees
sketch "Sketch1" plane through (0, 0, 0) normal (0, 0, 1) x (1, 0, 0)
  line L0 (-17.8333, 7.1333) -> (24.1667, 7.1333)
  line L1 (24.1667, 7.1333) -> (24.1667, -0.8667)
  line L2 (24.1667, -0.8667) -> (-17.8333, -0.8667)
  line L3 (-17.8333, -0.8667) -> (-17.8333, 7.1333)
  dimension "d1" = 42
  dimension "d2" = 42
  dimension "d3" = 8
  constraint horizontal L0
  constraint vertical L1
  constraint horizontal L2
  constraint vertical L3
  measures "d1" distance of L0.start L0.end
  measures "d2" distance of L0.start L0.end
  measures "d3" distance of L0 L2
extrude "Extrude1" add sketch "Sketch1" along normal blind 6
move_body "Move1" bodies 1 to x (1, 0, 0) y (0, 0, 1) z (0, -1, 0) at (0, 9.1333, 2.8667)
sketch "Sketch2" plane through (0, 3.1333, 0) normal (0, -1, 0) x (1, 0, 0)
  line L0 (-17.8333, 2) -> (24.1667, 2)
  line L1 (24.1667, 2) -> (24.1667, 10)
  line L2 (24.1667, 10) -> (-17.8333, 10)
  line L3 (-17.8333, 10) -> (-17.8333, 2)
  circle A0 centre (-12.2333, 6.245) radius 1.5
  circle A1 centre (18.5167, 6.245) radius 1.5
  dimension "d6" = 3
  dimension "d7" = 3
  dimension "d9" = 4.245
  dimension "d10" = 30.75
  dimension "d11" = 5.6
  measures "d6" diameter of A0
  measures "d7" diameter of A1
  measures "d9" distance of L0 A0.centre
  measures "d10" distance of A0.centre A1.centre
  measures "d11" distance of L3 A0.centre
extrude "Extrude2" cut sketch "Sketch2" against normal blind 26 contours A0 | A1
sketch "Sketch3" plane through (0, 0, 2) normal (0, 0, -1) x (1, 0, 0)
  line L0 (-17.8333, -9.1333) -> (24.1667, -9.1333)
  line L1 (24.1667, -9.1333) -> (24.1667, -3.1333)
  line L2 (24.1667, -3.1333) -> (-17.8333, -3.1333)
  line L3 (-17.8333, -3.1333) -> (-17.8333, -9.1333)
  circle A0 centre (-3.8333, -6.1333) radius 1.5
  circle A1 centre (11.1667, -6.1333) radius 1.5
  dimension "d14" = 3
  dimension "d15" = 3
  dimension "d16" = 15
  dimension "d17" = 13
  dimension "d19" = 3
  measures "d14" diameter of A0
  measures "d15" diameter of A1
  measures "d16" horizontal distance of A0.centre A1.centre
  measures "d17" distance of L1 A1.centre
  measures "d19" distance of L2 A1.centre
extrude "Extrude3" cut sketch "Sketch3" against normal blind 22 contours A0 | A1
extrude "Extrude4" cut 1 faces at (-17.8333, 5.1333, 7.3333) along direction (1, 0, 0) blind 1
extrude "Extrude5" add 1 faces at (-16.8333, 5.1333, 7.3333) along direction (-1, 0, 0) blind 1
extrude "Extrude6" cut 1 faces at (24.1667, 7.1333, 7.3333) along direction (-1, 0, 0) blind 1
equation "a = 4.245 mm"
equation "d9 = a"
equation "d10 = 28.23 mm + 2.52 mm"
equation "b = 3 mm"
equation "d19 = b"

design "Base 19x41x240 Wood"
part number: 2026-10-14-14-34-22-627
Autodesk Fusion 360 part; units mm, degrees
sketch "Sketch1" plane through (0, 0, 0) normal (0, 0, 1) x (1, 0, 0)
  line L0 (-28.3104, 11.1458) -> (-9.3104, 11.1458)
  line L1 (-9.3104, 11.1458) -> (-9.3104, -29.8542)
  line L2 (-9.3104, -29.8542) -> (-28.3104, -29.8542)
  line L3 (-28.3104, -29.8542) -> (-28.3104, 11.1458)
  dimension "d1" = 19
  dimension "d2" = 41
  constraint horizontal L0
  constraint vertical L1
  constraint horizontal L2
  constraint vertical L3
  measures "d1" distance of L0.start L0.end
  measures "d2" distance of L0.start L2.end
extrude "Extrude1" add sketch "Sketch1" along normal blind 240